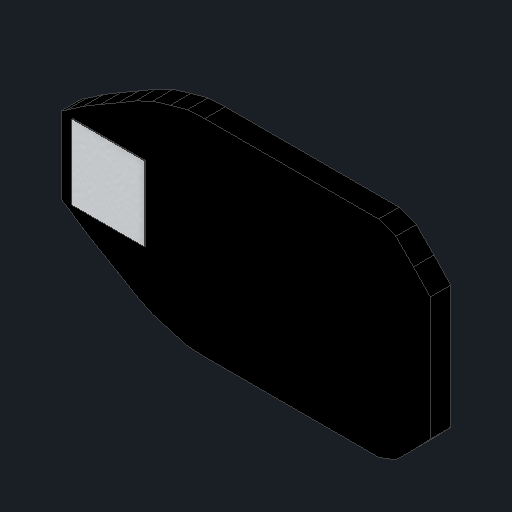
# Autodesk Inventor part: MobileDetect Pouch (approx)
Saved by Autodesk Inventor 2027.2 (Build 312334000, 334)
## iProperties
Created: 2026-11-06
Part Number: MobileDetect Pouch (approx)
Material: Generic
Description: DetectaChem MobileDetect pouch, outline from product image at 50.3 x 89.9 mm; thickness assumed
Document SubType Name: Modeling
Designer: isaac
Density: 1 g/cm^3
Appearance: Default
Author: isaac
Autodesk Inventor part; units mm, degrees
ref_plane "YZ Plane" through (0, 0, 0) normal (1, 0, 0) x (0, 1, 0)
ref_plane "XZ Plane" through (0, 0, 0) normal (0, 1, 0) x (-1, 0, 0)
sketch "Sketch1" plane through (0, 0, 0) normal (0, 0, 1) x (1, 0, 0)
  line L0 (0, -9.5) -> (0.95, -10)
  line L1 (0.95, -10) -> (5.2, -12.97)
  line L2 (5.2, -12.97) -> (9.4, -15.46)
  line L3 (9.4, -15.46) -> (13.7, -17.95)
  line L4 (13.7, -17.95) -> (17.9, -20.44)
  line L5 (17.9, -20.44) -> (22.1, -22.5)
  line L6 (22.1, -22.5) -> (26.4, -23.77)
  line L7 (26.4, -23.77) -> (30.6, -24.94)
  line L8 (30.6, -24.94) -> (34.8, -25.15)
  line L9 (34.8, -25.15) -> (77.2, -25.15)
  line L10 (77.2, -25.15) -> (81.4, -23.6)
  line L11 (81.4, -23.6) -> (85.7, -19.3)
  line L12 (85.7, -19.3) -> (89.8, -15)
  line L13 (89.8, -15) -> (89.8, 15)
  line L14 (89.8, 15) -> (85.7, 19.3)
  line L15 (85.7, 19.3) -> (81.4, 23.6)
  line L16 (81.4, 23.6) -> (77.2, 25.15)
  line L17 (77.2, 25.15) -> (34.8, 25.15)
  line L18 (34.8, 25.15) -> (30.6, 24.94)
  line L19 (30.6, 24.94) -> (26.4, 23.77)
  line L20 (26.4, 23.77) -> (22.1, 22.5)
  line L21 (22.1, 22.5) -> (17.9, 20.44)
  line L22 (17.9, 20.44) -> (13.7, 17.95)
  line L23 (13.7, 17.95) -> (9.4, 15.46)
  line L24 (9.4, 15.46) -> (5.2, 12.97)
  line L25 (5.2, 12.97) -> (0.95, 10)
  line L26 (0.95, 10) -> (0, 9.5)
  line L27 (0, 9.5) -> (0, -9.5)
  constraints: 56 end point
extrude "Body" add sketch "Sketch1" along normal blind 5
ref_plane "Work Plane1" through (0, 0, 5) normal (0, 0, 1) x (1, 0, 0)
sketch "Sketch2" plane through (0, 0, 5) normal (0, 0, 1) x (1, 0, 0)
  line L0 (2.6, -9.1) -> (20.3, -9.1)
  line L1 (20.3, -9.1) -> (20.3, 9.1)
  line L2 (20.3, 9.1) -> (2.6, 9.1)
  line L3 (2.6, 9.1) -> (2.6, -9.1)
  constraints: 8 end point, 2 parallel, 1 horizontal, 1 perpendicular
extrude "Pad" add sketch "Sketch2" along normal blind 0.2
body "Solid1"
